01_poise_v1_strip_and_pod (Autodesk Fusion 360 design; units mm, degrees)
part number: 2026-10-12-19-00-26-951
Autodesk Fusion 360 part; units mm, degrees
sketch "Tape Band" plane through (0, 0, 0) normal (0, 0, 1) x (1, 0, 0)
  line L0 (-76, -15) -> (76, -15)
  arc A0 (76, -15) -> (90, -1) centre (76, -1) ccw
  line L1 (90, -1) -> (90, 1)
  arc A1 (90, 1) -> (76, 15) centre (76, 1) ccw
  line L2 (76, 15) -> (-76, 15)
  arc A2 (-76, 15) -> (-90, 1) centre (-76, 1) ccw
  line L3 (-90, 1) -> (-90, -1)
  arc A3 (-90, -1) -> (-76, -15) centre (-76, -1) ccw
extrude "Extrude1" add sketch "Tape Band" along normal blind 0.6 makes body 1
sketch "Tape End" plane through (0, 0, 0) normal (0, 0, 1) x (1, 0, 0)
  ellipse E0 centre (-90, 0) end of major axis (-60, 0) minor radius 23
  line L0 (-120, 0) -> (-60, 0) construction
  line L1 (-90, 23) -> (-90, -23) construction
  constraint coincident E0 L0.start
  constraint coincident E0 L0.end
  constraint coincident E0 L1.start
  constraint coincident E0 L1.end
extrude "Extrude2" add sketch "Tape End" along normal blind 0.6 bodies 1
sketch "Tape End (1)" plane through (0, 0, 0) normal (0, 0, 1) x (1, 0, 0)
  ellipse E0 centre (90, 0) end of major axis (120, 0) minor radius 23
  line L0 (60, 0) -> (120, 0) construction
  line L1 (90, 23) -> (90, -23) construction
  constraint coincident E0 L0.start
  constraint coincident E0 L0.end
  constraint coincident E0 L1.start
  constraint coincident E0 L1.end
extrude "Extrude3" add sketch "Tape End (1)" along normal blind 0.6 bodies 1
sketch "Sensor Pad" plane through (0, 0, 0) normal (0, 0, 1) x (1, 0, 0)
  line L0 (-35, -8) -> (65, -8)
  arc A0 (65, -8) -> (70, -3) centre (65, -3) ccw
  line L1 (70, -3) -> (70, 3)
  arc A1 (70, 3) -> (65, 8) centre (65, 3) ccw
  line L2 (65, 8) -> (-35, 8)
  arc A2 (-35, 8) -> (-40, 3) centre (-35, 3) ccw
  line L3 (-40, 3) -> (-40, -3)
  arc A3 (-40, -3) -> (-35, -8) centre (-35, -3) ccw
extrude "Extrude4" add sketch "Sensor Pad" along normal blind 0.06 from surface at 0.6 separate body makes body 2
sketch "Trace 0" plane through (0, 0, 0) normal (0, 0, 1) x (1, 0, 0)
  line L0 (-36.5, -5.1) -> (66.5, -5.1)
  arc A0 (66.5, -5.1) -> (67, -4.6) centre (66.5, -4.6) ccw
  line L1 (67, -4.6) -> (67, -4.4)
  arc A1 (67, -4.4) -> (66.5, -3.9) centre (66.5, -4.4) ccw
  line L2 (66.5, -3.9) -> (-36.5, -3.9)
  arc A2 (-36.5, -3.9) -> (-37, -4.4) centre (-36.5, -4.4) ccw
  line L3 (-37, -4.4) -> (-37, -4.6)
  arc A3 (-37, -4.6) -> (-36.5, -5.1) centre (-36.5, -4.6) ccw
extrude "Extrude5" add sketch "Trace 0" along normal blind 0.04 from surface at 0.66 separate body makes body 3
sketch "Trace 1" plane through (0, 0, 0) normal (0, 0, 1) x (1, 0, 0)
  line L0 (-36.5, -0.6) -> (66.5, -0.6)
  arc A0 (66.5, -0.6) -> (67, -0.1) centre (66.5, -0.1) ccw
  line L1 (67, -0.1) -> (67, 0.1)
  arc A1 (67, 0.1) -> (66.5, 0.6) centre (66.5, 0.1) ccw
  line L2 (66.5, 0.6) -> (-36.5, 0.6)
  arc A2 (-36.5, 0.6) -> (-37, 0.1) centre (-36.5, 0.1) ccw
  line L3 (-37, 0.1) -> (-37, -0.1)
  arc A3 (-37, -0.1) -> (-36.5, -0.6) centre (-36.5, -0.1) ccw
extrude "Extrude6" add sketch "Trace 1" along normal blind 0.04 from surface at 0.66 separate body makes body 4
sketch "Trace 2" plane through (0, 0, 0) normal (0, 0, 1) x (1, 0, 0)
  line L0 (-36.5, 3.9) -> (66.5, 3.9)
  arc A0 (66.5, 3.9) -> (67, 4.4) centre (66.5, 4.4) ccw
  line L1 (67, 4.4) -> (67, 4.6)
  arc A1 (67, 4.6) -> (66.5, 5.1) centre (66.5, 4.6) ccw
  line L2 (66.5, 5.1) -> (-36.5, 5.1)
  arc A2 (-36.5, 5.1) -> (-37, 4.6) centre (-36.5, 4.6) ccw
  line L3 (-37, 4.6) -> (-37, 4.4)
  arc A3 (-37, 4.4) -> (-36.5, 3.9) centre (-36.5, 4.4) ccw
extrude "Extrude7" add sketch "Trace 2" along normal blind 0.04 from surface at 0.66 separate body makes body 5
sketch "Lead" plane through (0, 0, 0) normal (0, 0, 1) x (1, 0, 0)
  line L0 (-64.2, -1) -> (-39.8, -1)
  arc A0 (-39.8, -1) -> (-39, -0.2) centre (-39.8, -0.2) ccw
  line L1 (-39, -0.2) -> (-39, 0.2)
  arc A1 (-39, 0.2) -> (-39.8, 1) centre (-39.8, 0.2) ccw
  line L2 (-39.8, 1) -> (-64.2, 1)
  arc A2 (-64.2, 1) -> (-65, 0.2) centre (-64.2, 0.2) ccw
  line L3 (-65, 0.2) -> (-65, -0.2)
  arc A3 (-65, -0.2) -> (-64.2, -1) centre (-64.2, -0.2) ccw
extrude "Extrude8" add sketch "Lead" along normal blind 0.06 from surface at 0.6 separate body makes body 6
sketch "Dock" plane through (0, 0, 0) normal (0, 0, 1) x (1, 0, 0)
  circle A0 centre (-76, 0) radius 11.5
  circle A1 centre (-76, 0) radius 9.3
extrude "Extrude9" add sketch "Dock" along normal blind 0.7 from surface at 0.6 separate body makes body 7
sketch "Contact 0" plane through (0, 0, 0) normal (0, 0, 1) x (1, 0, 0)
  circle A0 centre (-71.5, 0) radius 0.9
extrude "Extrude10" add sketch "Contact 0" along normal blind 0.1 from surface at 0.6 separate body makes body 8
sketch "Contact 1" plane through (0, 0, 0) normal (0, 0, 1) x (1, 0, 0)
  circle A0 centre (-78.2, 3.9) radius 0.9
extrude "Extrude11" add sketch "Contact 1" along normal blind 0.1 from surface at 0.6 separate body makes body 9
sketch "Contact 2" plane through (0, 0, 0) normal (0, 0, 1) x (1, 0, 0)
  circle A0 centre (-78.2, -3.9) radius 0.9
extrude "Extrude12" add sketch "Contact 2" along normal blind 0.1 from surface at 0.6 separate body makes body 10
sketch "Pod Coin" plane through (0, 0, 0) normal (0, 0, 1) x (1, 0, 0)
  circle A0 centre (-76, 0) radius 9
extrude "Extrude13" add sketch "Pod Coin" along normal blind 2 from surface at 0.7 separate body makes body 11
fillet "Fillet1" radius 0.9 1 edges at (-84.3909, -3.2545, 2.7) on bodies 11
sketch "LED" plane through (0, 0, 0) normal (0, 0, 1) x (1, 0, 0)
  circle A0 centre (-76, 4.5) radius 0.7
extrude "Extrude14" add sketch "LED" along normal blind 0.04 from surface at 2.7 separate body makes body 12
named bodies: "Smart Tape", "Stretch Sensor", "Electrode 0", "Electrode 1", "Electrode 2", "Sensor Lead", "Snap Dock", "Contact 0", "Contact 1", "Contact 2", "Pod Coin", "Status LED"
